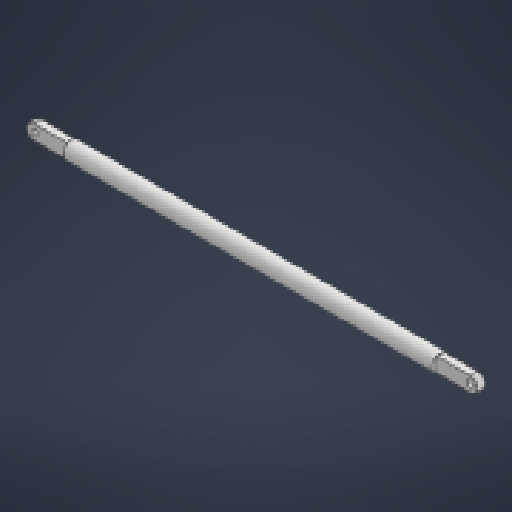
# Autodesk Inventor part: barillaBrazo
Saved by Autodesk Inventor 2027.1 (Build 311270010, 270A)
## iProperties
Created: 2026-11-02
Part Number: barillaBrazo
Material: Genérico
Document SubType Name: Modeling
Designer: MANGEL
Density: 1 g/cm^3
Appearance: Valor por defecto
Author: MANGEL
Autodesk Inventor part; units mm, degrees
ref_plane "YZ Plane" through (0, 0, 0) normal (1, 0, 0) x (0, 1, 0)
ref_plane "XZ Plane" through (0, 0, 0) normal (0, 1, 0) x (-1, 0, 0)
ref_plane "XY Plane" through (0, 0, 0) normal (0, 0, 1) x (1, 0, 0)
sketch "Boceto2" plane through (0, 0, 0) normal (0, 0, 1) x (1, 0, 0)
  line L0 (-147.5, 0) -> (147.5, 0) construction
  line L1 (-147.5, -5) -> (147.5, -5)
  line L2 (147.5, 5) -> (-147.5, 5)
  arc A0 (-147.5, 5) -> (-147.5, -5) centre (-147.5, 0) ccw
  arc A1 (147.5, -5) -> (147.5, 5) centre (147.5, 0) ccw
  point P0 (0, 0)
  point P1 (152.5, 0)
  point P2 (-152.5, 0)
  dimension "d3" = 10
  dimension "d4" = 305
  constraints: 8 end point, 6 point on circle, 4 tangent, 2 centre point, 1 horizontal, 1 midpoint, 1 parallel
  measures "d3" distance between parallel lines of L1 L2
  measures "d4" distance of point (152.5, 0) point (-152.5, 0)
extrude "Extrusión2" add sketch "Boceto2" along normal mid plane 5
sketch "Boceto3" plane through (0, 0, 0) normal (1, 0, 0) x (0, 1, 0)
  circle A0 centre (0, 0) radius 5.5902
  point P0 (5, -2.5)
  constraints: 1 coincident, 3 other
extrude "Extrusión3" add sketch "Boceto3" along normal mid plane 250
sketch "Boceto4" plane through (0, 0, 2.5) normal (0, 0, 1) x (1, 0, 0)
  arc A0 (-147.5, 5) -> (-147.5, -5) centre (-147.5, 0) ccw projected
  circle A1 centre (-147.5, 0) radius 2
  arc A2 (147.5, -5) -> (147.5, 5) centre (147.5, 0) ccw projected
  circle A3 centre (147.5, 0) radius 2
  point P0 (0, 0)
  dimension "d10" = 4
  dimension "d11" = 4
  constraints: 2 centre point, 2 coincident
  measures "d10" diameter of A1
  measures "d11" diameter of A3
extrude "Extrusión4" cut sketch "Boceto4" along normal mid plane 250
